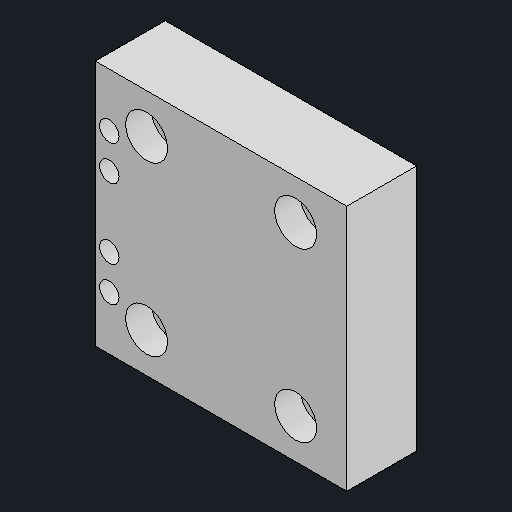
# Autodesk Inventor part: SBI20SL-bellows-adapter
Saved by Autodesk Inventor 2027.1 (Build 311270010, 270A)
## iProperties
Created: 2026-11-14
Part Number: SBI20SL-bellows-adapter
Material: Generic
Description: 15 mm riser; four SBC M5 screws and two tapped clamp-foot connections per side
Document SubType Name: Modeling
Designer: queezz
Density: 1 g/cm^3
Appearance: Default
Author: queezz
Autodesk Inventor part; units mm, degrees
ref_plane "Riser footprint plane" through (0, 0, 0) normal (0, 0, 1) x (1, 0, 0)
sketch "Riser footprint" plane through (0, 0, 0) normal (0, 0, 1) x (1, 0, 0)
  line L0 (-27, -26.5) -> (27, -26.5)
  line L1 (27, -26.5) -> (27, 26.5)
  line L2 (27, 26.5) -> (-27, 26.5)
  line L3 (-27, 26.5) -> (-27, -26.5)
  constraints: 8 end point, 2 parallel, 1 horizontal, 1 perpendicular
extrude "Preserve original carriage height" add sketch "Riser footprint" along normal blind 15
ref_plane "M5 block clearances layout plane" through (0, 0, 15) normal (0, 0, 1) x (1, 0, 0)
sketch "M5 block clearances layout" plane through (0, 0, 15) normal (0, 0, 1) x (1, 0, 0)
  circle A0 centre (-16, -18) radius 2.75
  circle A1 centre (-16, 18) radius 2.75
  circle A2 centre (16, -18) radius 2.75
  circle A3 centre (16, 18) radius 2.75
  constraints: 4 centre point
extrude "M5 block clearances" cut sketch "M5 block clearances layout" against normal blind 15
ref_plane "M5 block head recesses layout plane" through (0, 0, 15) normal (0, 0, 1) x (1, 0, 0)
sketch "M5 block head recesses layout" plane through (0, 0, 15) normal (0, 0, 1) x (1, 0, 0)
  circle A0 centre (-16, -18) radius 4.5
  circle A1 centre (-16, 18) radius 4.5
  circle A2 centre (16, -18) radius 4.5
  circle A3 centre (16, 18) radius 4.5
  constraints: 4 centre point
extrude "M5 block head recesses" cut sketch "M5 block head recesses layout" against normal blind 5.5
ref_plane "Foot M5 tap pilots for single and centre foot layout plane" through (0, 0, 15) normal (0, 0, 1) x (1, 0, 0)
sketch "Foot M5 tap pilots for single and centre foot layout" plane through (0, 0, 15) normal (0, 0, 1) x (1, 0, 0)
  circle A0 centre (-24, -15) radius 2.1
  circle A1 centre (-24, -7.5) radius 2.1
  circle A2 centre (-24, 7.5) radius 2.1
  circle A3 centre (-24, 15) radius 2.1
  constraints: 4 centre point
extrude "Foot M5 tap pilots for single and centre foot" cut sketch "Foot M5 tap pilots for single and centre foot layout" against normal blind 15
body "Solid1"
